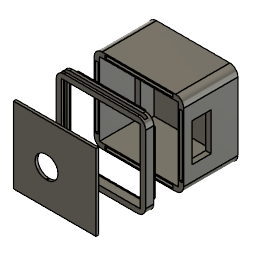
E_Case_sensor_pressao (Autodesk Fusion 360 design; units mm, degrees)
Autodesk Fusion 360 part; units mm, degrees
sketch "Esboço3" plane through (0, 0, 0) normal (0, 1, 0) x (1, 0, 0)
  line L0 (0, 0) -> (-16.5, 0)
  line L1 (-16.5, 0) -> (-16.5, -10)
  line L2 (-12.5, -1.9144) -> (0, -1.9144)
  line L3 (-16.5, -10) -> (-16.5, -20)
  line L4 (-16.5, -20) -> (-14.5, -20)
  line L5 (-12.5, -19.9948) -> (-14.5, -20)
  line L6 (0, 0) -> (0, -1.9144)
  line L7 (12.5, -1.9144) -> (0, -1.9144)
  line L8 (16.5, 0) -> (16.5, -10)
  line L9 (16.5, -20) -> (14.5, -20)
  line L10 (16.5, -10) -> (16.5, -20)
  line L11 (12.5, -19.9948) -> (14.5, -20)
  line L12 (0, 0) -> (16.5, 0)
  line L13 (16.5, 0) -> (-16.5, 0)
  line L14 (-16.5, 0) -> (-16.5, -20)
  line L15 (-16.5, -20) -> (16.5, -20)
  line L16 (16.5, -20) -> (16.5, 0)
  line L17 (-14.5, -6.9144) -> (-14.5, -15.0948)
  line L18 (14.5, -6.9144) -> (14.5, -15.0948)
  line L19 (-14.5, -6.9144) -> (-12.5, -6.9144)
  line L20 (-12.5, -6.9144) -> (-12.5, -1.9144)
  line L21 (-14.5, -6.9144) -> (-12.5, -6.9144)
  line L22 (-12.5, -6.9144) -> (-12.5, -1.9144)
  line L23 (12.5, -6.9144) -> (12.5, -1.9144)
  line L24 (14.5, -6.9144) -> (12.5, -6.9144)
  line L25 (-14.5, -20) -> (-14.5, -17.0948)
  line L26 (14.5, -20) -> (14.5, -17.0948)
  line L27 (-14.5, -15.0948) -> (-14.5, -17.0948)
  line L28 (14.5, -15.0948) -> (14.5, -17.0948)
  point P0 (-14.5, -20)
  point P1 (14.5, -20)
  dimension "d3" = 16.5
  dimension "d29" = 20
  dimension "d31" = 2
  dimension "d32" = 2
  constraint coincident L0.start L6.start
  constraint horizontal L0
  constraint perpendicular L0 L1
  constraint parallel L0 L2
  constraint vertical L3
  constraint horizontal L4
  constraint coincident P0 L4.end
  constraint horizontal L13
  constraint vertical L14
  constraint horizontal L15
  constraint vertical L16
  constraint perpendicular L17 L19
  constraint perpendicular L2 L20
  constraint symmetric L6 L17.start L18.start
  constraint symmetric L6 L19.end L23.start
  constraint symmetric L6 L2.start L7.start
  measures "d3" distance of L0.start L0.end
  measures "d29" distance of L3.end L0.end
  measures "d31" distance of L17.start L19.end
  measures "d32" distance of L17.start L19.end
  measures "d76" distance of L3.end
  measures "d77" distance of L3.end
  measures "d79" distance of L3.end
  measures "d80" distance of L3.end
  measures "d81" distance of L3.end
extrude "Extrusão1" add sketch "Esboço3" along normal blind 27 contours L0 L1 L2 L3 L4 L6 L13 L14 L15 L17 L19 L20 L21 L22 L25 L27 | L6 L7 L8 L9 L10 L12 L13 L15 L16 L18 L23 L24 L26 L28 makes body 1
extrude "Extrusão2" add sketch "Esboço3" against normal blind 2 bodies 1
sketch "Esboço4" plane through (0, 0, 0) normal (0, 0, -1) x (-1, 0, 0)
  line L0 (16.5, -2) -> (16.5, 27)
  line L1 (16.5, 27) -> (-16.5, 27)
  line L2 (-16.5, 27) -> (-16.5, -2)
  line L3 (-16.5, -2) -> (16.5, -2)
  line L4 (0, 0) -> (3.5, 0)
  line L5 (3.5, 0) -> (3.5, 23)
  line L6 (3.5, 23) -> (0, 23)
  line L7 (-3.5, 0) -> (-3.5, 23)
  line L8 (-3.5, 23) -> (0, 23)
  line L9 (0, 0) -> (-3.5, 0)
  dimension "d24" = 23
  dimension "d25" = 3.5
  constraint horizontal L4
  constraint vertical L5
  constraint horizontal L6
  constraint coincident L4.start L9.start
  measures "d24" distance of L4.end L5.end
  measures "d25" distance of L5.end L6.end
ref_plane "Plano de trabalho1" through (0, 12.5, -3) normal (0, 0, -1) x (-1, 0, 0)
sketch "Esboço5" plane through (0, 0, -3) normal (0, 0, -1) x (-1, 0, 0)
  line L0 (0, 0) -> (-4, 0)
  line L1 (-4, 0) -> (-4, 23)
  line L2 (-4, 23) -> (0, 23)
  line L3 (4, 23) -> (0, 23)
  line L4 (0, 0) -> (4, 0)
  line L5 (4, 0) -> (4, 23)
  dimension "d27" = 4
  dimension "d28" = 23
  constraint horizontal L0
  constraint vertical L1
  constraint horizontal L2
  constraint coincident L0.start L4.start
  measures "d27" distance of L0.start L0.end
  measures "d28" distance of L0.start L2.end
loft "Transição1" add profiles "Esboço4", "Esboço5" section 1 contours L4 L5 L6 L7 L8 L9 section 2 bodies 1
sketch "Esboço7" plane through (0, 27, 0) normal (0, 1, 0) x (-1, 0, 0)
  line L0 (-14.5, 20) -> (-16.5, 20)
  line L1 (-16.5, 20) -> (-16.5, 0)
  line L2 (-16.5, 0) -> (16.5, 0)
  line L3 (16.5, 0) -> (16.5, 20)
  line L4 (16.5, 20) -> (14.5, 20)
  line L5 (14.5, 20) -> (14.5, 6.9144)
  line L6 (14.5, 6.9144) -> (12.5, 6.9144)
  line L7 (12.5, 6.9144) -> (12.5, 1.9144)
  line L8 (12.5, 1.9144) -> (-12.5, 1.9144)
  line L9 (-12.5, 1.9144) -> (-12.5, 6.9144)
  line L10 (-12.5, 6.9144) -> (-14.5, 6.9144)
  line L11 (-14.5, 6.9144) -> (-14.5, 20)
  line L12 (16.5, 0) -> (12.5, 0)
  line L13 (12.5, 20) -> (16.5, 20)
  line L14 (16.5, 20) -> (16.5, 0)
  line L15 (-16.5, 0) -> (-12.5, 0)
  line L16 (-12.5, 20) -> (-16.5, 20)
  line L17 (-16.5, 20) -> (-16.5, 0)
  line L18 (16.5, 0) -> (-16.5, 0)
  line L19 (-16.5, 0) -> (-16.5, 4)
  line L20 (16.5, 4) -> (16.5, 0)
  line L21 (12.5, 20) -> (-12.5, 20)
  dimension "d34" = 20
  dimension "d35" = 20
  dimension "d36" = 4
  constraint horizontal L12
  constraint horizontal L13
  constraint vertical L14
  constraint coincident L2.end L3.start
  constraint horizontal L15
  constraint horizontal L16
  constraint vertical L17
  constraint coincident L1.end L2.start
  constraint horizontal L18
  constraint vertical L19
  constraint vertical L20
  measures "d34" distance of L2.end L3.end
  measures "d35" distance of L1.end L0.end
  measures "d36" distance of L2.end L20.start
extrude "Extrusão3" add sketch "Esboço7" along normal blind 2 bodies 1
fillet "Arredondamento1" radius 3 1 edges at (-16.5, 29, 10) on bodies 1
fillet "Arredondamento2" radius 3 1 edges at (16.5, 29, 10) on bodies 1
fillet "Arredondamento3" radius 3 1 edges at (16.5, -2, 10) on bodies 1
fillet "Arredondamento4" radius 3 1 edges at (-16.5, -2, 10) on bodies 1
sketch "Esboço12" plane through (0, 0, 20) normal (0, 0, 1) x (1, 0, 0)
  line L0 (14.5, 27) -> (14.5, 0)
  line L1 (14.5, 0) -> (-14.5, 0)
  line L2 (-14.5, 0) -> (-14.5, 27)
  line L3 (-14.5, 27) -> (14.5, 27)
  arc A0 (-16.5, 1) -> (-13.5, -2) centre (-13.5, 1) ccw
  line L4 (-13.5, -2) -> (13.5, -2)
  arc A1 (13.5, -2) -> (16.5, 1) centre (13.5, 1) ccw
  line L5 (16.5, 1) -> (16.5, 26)
  arc A2 (16.5, 26) -> (13.5, 29) centre (13.5, 26) ccw
  line L6 (13.5, 29) -> (-13.5, 29)
  arc A3 (-13.5, 29) -> (-16.5, 26) centre (-13.5, 26) ccw
  line L7 (-16.5, 26) -> (-16.5, 1)
extrude "Extrusão6" add 1 faces at (4.5, -0.6667, 20) along direction (0, 0, 1) blind 3 separate body on bodies 1 makes body 2
copy_body "Corpo -> Componente1" bodies 1 removing the originals makes body 3 in component "Case"
copy_body "Corpo -> Componente2" bodies 2 removing the originals makes body 4 in component "Tampa"
ref_plane "Plano de trabalho4" through (0, 13.5, 21) normal (0, 0, 1) x (1, 0, 0)
sketch "Esboço13" plane through (0, 0, 21) normal (0, 0, 1) x (1, 0, 0)
  line L0 (0, 0) -> (-15.3, 0)
  line L1 (-15.3, 0) -> (-15.3, 29)
  line L2 (-15.3, 29) -> (0, 29)
  line L3 (0, 29) -> (0, 0)
  line L4 (15.3, 29) -> (0, 29)
  line L5 (15.3, 0) -> (15.3, 29)
  line L6 (0, 0) -> (15.3, 0)
  line L7 (-15.3, 0) -> (15.3, 0)
  line L8 (15.3, 0) -> (15.3, -1)
  line L9 (15.3, -1) -> (-15.3, -1)
  line L10 (-15.3, -1) -> (-15.3, 0)
  dimension "d60" = 15.3
  dimension "d61" = 29
  dimension "d64" = 1
  constraint horizontal L0
  constraint vertical L1
  constraint horizontal L2
  constraint vertical L3
  constraint coincident L0.start L3.end
  constraint symmetric L0.start L3 L6.start
  constraint symmetric L0.end L3 L5.start
  constraint symmetric L1.end L3 L4.start
  constraint symmetric L2.end L3 L4.end
  constraint horizontal L7
  constraint vertical L8
  constraint horizontal L9
  constraint vertical L10
  measures "d60" distance of L0.start L0.end
  measures "d61" distance of L0.start L2.end
  measures "d64" distance of L0.end L9.end
extrude "Extrusão1'" cut sketch "Esboço13" along normal blind 1.2 contours L0 L1 L2 L3 L7 | L3 L4 L5 L6 L7 bodies 4 in component "Tampa"
ref_plane "Plano de trabalho5" through (0, 13.5, 50) normal (0, 0, 1) x (1, 0, 0)
sketch "Esboço15" plane through (0, 0, 50) normal (0, 0, 1) x (1, 0, 0)
  line L0 (0, 0) -> (-15.2, 0)
  line L1 (-15.2, 0) -> (-15.2, 28)
  line L2 (-15.2, 28) -> (0, 28)
  line L3 (0, 28) -> (0, 0)
  line L4 (15.2, 28) -> (0, 28)
  line L5 (15.2, 0) -> (15.2, 28)
  line L6 (0, 0) -> (15.2, 0)
  dimension "d66" = 15.2
  dimension "d67" = 28
  constraint horizontal L0
  constraint vertical L1
  constraint horizontal L2
  constraint vertical L3
  constraint coincident L0.start L3.end
  constraint symmetric L0.start L3 L6.start
  constraint symmetric L0.end L3 L5.start
  constraint symmetric L1.end L3 L4.start
  constraint symmetric L2.end L3 L4.end
  measures "d66" distance of L0.start L0.end
  measures "d67" distance of L0.start L2.end
extrude "Extrusão7" add sketch "Esboço15" along normal blind 1 separate body makes body 5
copy_body "Corpo -> Componente3" bodies 5 removing the originals makes body 6 in component "Face"
sketch "Esboço16" plane through (0, 29, 0) normal (0, 1, 0) x (-1, 0, 0)
  line L0 (-13.5, 20) -> (-13.5, 0)
  line L1 (-13.5, 0) -> (13.5, 0)
  line L2 (13.5, 0) -> (13.5, 20)
  line L3 (13.5, 20) -> (-13.5, 20)
  line L4 (13.5, 20) -> (-13.5, 20) construction
  line L5 (-13.5, 20) -> (-13.5, 0) construction
  line L6 (-13.5, 0) -> (13.5, 0) construction
  line L7 (13.5, 0) -> (13.5, 20) construction
  dimension "d70" = 4
  constraint coincident L1.end
  constraint coincident L0.start
sketch "Esboço1" plane through (0, 0, 20) normal (0, 0, -1) x (-1, 0, 0) in component "Tampa"
  line L0 (-14.5, 0) -> (-14.5, 27)
  line L1 (-14.5, 27) -> (14.5, 27)
  line L2 (14.5, 27) -> (14.5, 0)
  line L3 (14.5, 0) -> (-14.5, 0)
  arc A0 (13.5, -2) -> (16.5, 1) centre (13.5, 1) ccw
  line L4 (16.5, 1) -> (16.5, 26)
  arc A1 (16.5, 26) -> (13.5, 29) centre (13.5, 26) ccw
  line L5 (13.5, 29) -> (-13.5, 29)
  arc A2 (-13.5, 29) -> (-16.5, 26) centre (-13.5, 26) ccw
  line L6 (-16.5, 26) -> (-16.5, 1)
  arc A3 (-16.5, 1) -> (-13.5, -2) centre (-13.5, 1) ccw
  line L7 (-13.5, -2) -> (13.5, -2)
  line L8 (-14.5, 27) -> (-14.5, 25)
  line L9 (-14.5, 25) -> (-15, 25)
  line L10 (-15, 25) -> (-16, 25)
  line L11 (-16, 25) -> (-16, 2)
  line L12 (-16, 2) -> (-15, 2)
  line L13 (-15, 2) -> (-15, 25)
  line L14 (0, 0) -> (0, 29)
  line L15 (15, 25) -> (16, 25)
  line L16 (15, 2) -> (15, 25)
  line L17 (16, 25) -> (16, 2)
  line L18 (16, 2) -> (15, 2)
  line L19 (-14.5, 0) -> (-12.5, 0)
  line L20 (-12.5, 0) -> (-12.5, -0.5)
  line L21 (-12.5, -0.5) -> (12.5, -0.5)
  line L22 (12.5, -0.5) -> (12.5, -1.5)
  line L23 (12.5, -1.5) -> (-12.5, -1.5)
  line L24 (-12.5, -1.5) -> (-12.5, -0.5)
  line L25 (-14.5, 13.5) -> (14.5, 13.5)
  line L26 (-12.5, 27.5) -> (12.5, 27.5)
  line L27 (-12.5, 28.5) -> (-12.5, 27.5)
  line L28 (12.5, 28.5) -> (-12.5, 28.5)
  line L29 (12.5, 27.5) -> (12.5, 28.5)
  dimension "d74" = 2
  dimension "d75" = 0.5
  dimension "d76" = 1
  dimension "d77" = 23
  dimension "d78" = 2
  dimension "d79" = 0.5
  dimension "d80" = 25
  dimension "d81" = 1
  constraint coincident L0.end L1.start
  constraint perpendicular L1 L8
  constraint perpendicular L6 L9
  constraint horizontal L10
  constraint vertical L11
  constraint horizontal L12
  constraint vertical L13
  constraint coincident L14.start origin
  constraint midpoint L5 L14.end
  constraint symmetric L9.end L14 L15.start
  constraint symmetric L10.end L14 L15.end
  constraint symmetric L11.end L14 L17.end
  constraint symmetric L12.end L14 L16.start
  constraint coincident L0.start L3.end
  constraint perpendicular L0 L19
  constraint perpendicular L19 L20
  constraint horizontal L21
  constraint vertical L22
  constraint horizontal L23
  constraint vertical L24
  constraint midpoint L0 L25.start
  constraint midpoint L2 L25.end
  constraint symmetric L20.end L25 L26.start
  constraint symmetric L21.end L25 L26.end
  constraint symmetric L22.end L25 L28.start
  constraint symmetric L23.end L25 L27.start
  measures "d74" distance of L0.end L8.end
  measures "d75" distance of L8.end L9.end
  measures "d76" distance of L9.end L10.end
  measures "d77" distance of L9.end L12.end
  measures "d78" distance of L0.start L19.end
  measures "d79" distance of L19.end L20.end
  measures "d80" distance of L20.end L21.end
  measures "d81" distance of L20.end L23.end
extrude "Extrusão2'" add sketch "Esboço1" along normal blind 1 contours L10 L11 L12 L13 | L14 L26 L27 L28 | L14 L26 L28 L29 | L15 L16 L17 L18 | L21 L22 L23 L24 bodies 4 in component "Tampa"
sketch "Esboço1 (2)" plane through (0, 0, 20) normal (0, 0, 1) x (1, 0, 0) in component "Case"
  line L0 (14.5, 27) -> (14.5, 0)
  line L1 (14.5, 0) -> (-14.5, 0)
  line L2 (-14.5, 0) -> (-14.5, 27)
  line L3 (-14.5, 27) -> (14.5, 27)
  arc A0 (-16.5, 1) -> (-13.5, -2) centre (-13.5, 1) ccw
  line L4 (-13.5, -2) -> (13.5, -2)
  arc A1 (13.5, -2) -> (16.5, 1) centre (13.5, 1) ccw
  line L5 (16.5, 1) -> (16.5, 26)
  arc A2 (16.5, 26) -> (13.5, 29) centre (13.5, 26) ccw
  line L6 (13.5, 29) -> (-13.5, 29)
  arc A3 (-13.5, 29) -> (-16.5, 26) centre (-13.5, 26) ccw
  line L7 (-16.5, 26) -> (-16.5, 1)
  line L8 (12.5, 28.5) -> (-12.5, 28.5)
  line L9 (-12.5, 27.5) -> (12.5, 27.5)
  line L10 (-12.5, 28.5) -> (-12.5, 27.5)
  line L11 (12.5, 27.5) -> (12.5, 28.5)
extrude "Extrusão2''" cut sketch "Esboço1 (2)" against normal blind 1 contours L8 L9 L10 L11 bodies 3 in component "Case"
sketch "Esboço2" plane through (0, 0, 20) normal (0, 0, -1) x (-1, 0, 0) in component "Case"
extrude "Extrusão3'" cut sketch "Esboço1" along normal blind 1 contours L10 L11 L12 L13 | L15 L16 L17 L18 | L21 L22 L23 L24 bodies 3 in component "Case"
extrude "Extrusão3''" cut sketch "Esboço1" along normal blind 1 contours L10 L11 L12 L13 | L15 L16 L17 L18 | L21 L22 L23 L24 bodies 4 in component "Tampa"
extrude "Extrusão4" add sketch "Esboço1" along normal blind 1 contours L10 L11 L12 L13 | L15 L16 L17 L18 | L21 L22 L23 L24 bodies 4 in component "Tampa"
sketch "Esboço17" plane through (0, 0, 51) normal (0, 0, 1) x (1, 0, 0)
  line L0 (-15.2, 0) -> (15.2, 0)
  line L1 (15.2, 0) -> (15.2, 28)
  line L2 (15.2, 28) -> (-15.2, 28)
  line L3 (-15.2, 28) -> (-15.2, 0)
  line L4 (-15.2, 0) -> (15.2, 0)
  line L5 (15.2, 0) -> (15.2, 9)
  line L6 (-2.8, 9) -> (-3.2, 9)
  line L7 (-15.2, 9) -> (-15.2, 0)
  line L8 (-15.2, 28) -> (15.2, 28)
  line L9 (15.2, 28) -> (15.2, 17)
  line L10 (-2.8, 17) -> (-3.2, 17)
  line L11 (-15.2, 17) -> (-15.2, 28)
  line L12 (-15.2, 28) -> (-7.2, 28)
  line L13 (-7.2, 13) -> (-15.2, 13)
  line L14 (-15.2, 13) -> (-15.2, 28)
  line L15 (15.2, 28) -> (1.2, 28)
  line L16 (1.2, 0) -> (15.2, 0)
  line L17 (15.2, 0) -> (15.2, 28)
  arc A0 (-3.2, 17) -> (-7.2, 13) centre (-3.2, 13) ccw
  arc A1 (-7.2, 13) -> (-3.2, 9) centre (-3.2, 13) ccw
  arc A2 (-2.8, 9) -> (1.2, 13) centre (-2.8, 13) ccw
  arc A3 (1.2, 13) -> (-2.8, 17) centre (-2.8, 13) ccw
  dimension "d92" = 9
  dimension "d93" = 11
  dimension "d94" = 8
  dimension "d95" = 14
  dimension "d98" = 4
  constraint horizontal L4
  constraint vertical L5
  constraint horizontal L6
  constraint vertical L7
  constraint coincident L0.start L3.end
  constraint horizontal L8
  constraint vertical L9
  constraint horizontal L10
  constraint vertical L11
  constraint coincident L1 L9.end
  constraint coincident L2.end L3.start
  constraint horizontal L12
  constraint horizontal L13
  constraint vertical L14
  constraint horizontal L15
  constraint horizontal L16
  constraint vertical L17
  constraint coincident L11.start L10
  constraint tangent L10 A0
  constraint coincident L7.start L6
  constraint tangent L6 A1
  constraint equal A0 A1
  constraint coincident L13.start A0.end
  constraint coincident L5.end L6
  constraint tangent L6 A2
  constraint equal A0 A2
  constraint coincident L9.end L10
  constraint tangent L10 A3
  constraint equal A0 A3
  constraint coincident A2.end A3.start
  measures "d92" distance of L0.start L7.start
  measures "d93" distance of L2.end L11.start
  measures "d94" distance of L2.end L12.end
  measures "d95" distance of L1.end L15.end
  measures "d98" radius of A0
extrude "Extrusão1''" cut sketch "Esboço17" against normal blind 1 contours L6 L10 A0 A1 A2 A3 bodies 6 in component "Face"
sketch "Esboço18" plane through (16.5, 0, 0) normal (1, 0, 0) x (0, 0, -1)
  line L0 (-20, 1) -> (0, 1)
  line L1 (0, 1) -> (0, 26)
  line L2 (0, 26) -> (-20, 26)
  line L3 (-20, 26) -> (-20, 1)
  line L4 (-20, 13.5) -> (-13.4, 13.5)
  line L5 (-9.9, 6.5) -> (-16.9, 6.5)
  line L6 (-16.9, 6.5) -> (-16.9, 20.5)
  line L7 (-16.9, 20.5) -> (-9.9, 20.5)
  line L8 (-9.9, 20.5) -> (-9.9, 6.5)
  line L9 (-9.9, 6.5) -> (-16.9, 20.5) construction
  line L10 (-16.9, 6.5) -> (-9.9, 20.5) construction
  point P0 (-13.4, 13.5)
  dimension "d99" = 6.6
  dimension "d100" = 7
  dimension "d101" = 14
  constraint midpoint L3 L4.start
  constraint perpendicular L3 L4
  constraint horizontal L5
  constraint perpendicular L5 L6
  constraint parallel L5 L7
  constraint parallel L6 L8
  constraint coincident L9 P0
  constraint coincident L10 P0
  constraint coincident P0 L4.end
  measures "d99" distance of L4.start P0
  measures "d100" distance of L6.end L7.end
  measures "d101" distance of L5.end L6.end
extrude "Extrusão4'" cut sketch "Esboço18" against normal blind 2 contours L5 L6 L7 L8 bodies 3 in component "Case"
component "Case" placed x (1, 0, 0) y (0, 1, 0) z (0, 0, 1) at (0, 0, 0)
component "Tampa" placed x (1, 0, 0) y (0, 1, 0) z (0, 0, 1) at (0, 0, 11)
component "Face" placed x (1, 0, 0) y (0, 1, 0) z (0, 0, 1) at (0, 0, 0)
equation "d71 = 'Pressure sensor'"
